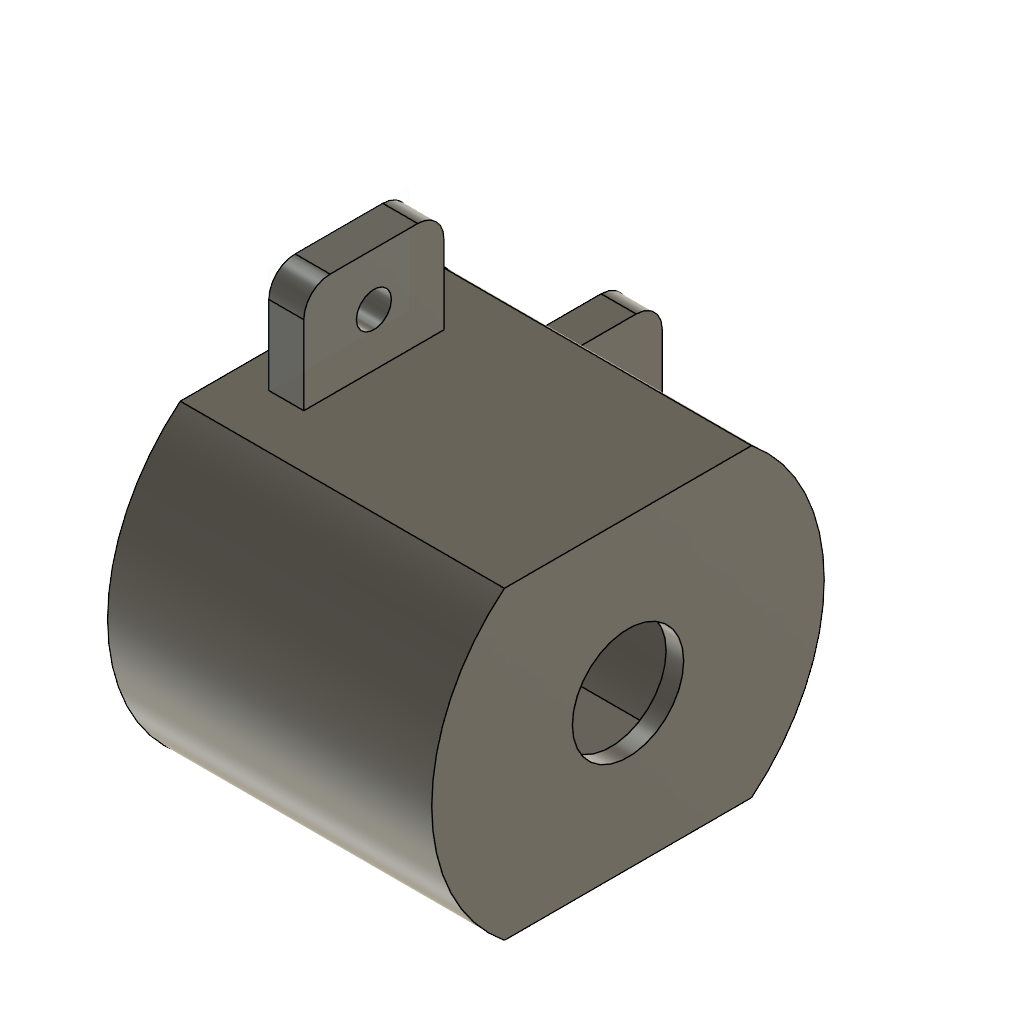
motorhalterung F-130 (Autodesk Fusion 360 design; units mm, degrees)
part number: 2026-11-07-18-57-53-680
Autodesk Fusion 360 part; units mm, degrees
sketch "Skizze1" plane through (0, 0, 0) normal (0, 0, 1) x (1, 0, 0)
  line L0 (0, 0) -> (26, 0)
  line L1 (26, 0) -> (26, 21)
  line L2 (26, 21) -> (0, 21)
  line L3 (0, 21) -> (0, 0)
  dimension "d1" = 21
  constraint coincident L0.start L3.end
  constraint horizontal L0
  constraint perpendicular L0 L1
  constraint perpendicular L1 L2
  constraint perpendicular L2 L3
  measures "d1" distance of L0.end L1.end
sketch "Skizze2" plane through (0, 0, 0) normal (0, 0, 1) x (1, 0, 0)
sketch "Skizze3" plane through (0, 0, 0) normal (1, 0, 0) x (0, 1, 0)
sketch "Skizze4" plane through (0, 0, 0) normal (1, 0, 0) x (0, 1, 0)
sketch "Skizze5" plane through (0, 0, 0) normal (1, 0, 0) x (0, 1, 0)
  line L0 (-6.6895, 0) -> (-6.6895, 7.7)
  line L1 (-6.6895, 0) -> (-6.6895, -7.7)
  line L2 (-6.6895, 7.7) -> (6.6895, 7.7)
  line L3 (-6.6895, -7.7) -> (6.6895, -7.7)
  line L4 (6.6895, 7.7) -> (6.6895, -7.7)
  arc A0 (-6.6895, 7.7) -> (-6.6895, -7.7) centre (0, 0) ccw
  arc A1 (6.6895, -7.7) -> (6.6895, 7.7) centre (0, 0) ccw
  dimension "d10" = 7.7
  dimension "d11" = 20.4
  constraint vertical L0
  constraint coincident A0.centre A1.centre
  constraint parallel L0 L1
  constraint perpendicular L0 L2
  constraint perpendicular L1 L3
  constraint concentric A0 A1
  measures "d10" distance of L0.start L0.end
  measures "d11" diameter of A0
extrude "Extrusion2" add sketch "Skizze5" along normal blind 17.5
shell "Schale1" thickness 1 outward yes removed faces 1 at (0, -2.914, 2.5667)
hole "Bohrung1" at (18.5, 0, 0) direction (-1, 0, 0) diameter 6.35 depth 5 tip angle 118
sketch "Skizze6" plane through (0, 0, 8.7) normal (0, 0, 1) x (-1, 0, 0)
  line L0 (0, -7.0533) -> (0, 7.0533)
  line L1 (0, 7.0533) -> (-18.5, 7.0533)
  line L2 (-18.5, 7.0533) -> (-18.5, -7.0533)
  line L3 (-18.5, -7.0533) -> (0, -7.0533)
  line L4 (-2, -4) -> (-4, -4)
  line L5 (-4, -4) -> (-4, 4)
  line L6 (-4, 4) -> (-2, 4)
  line L7 (-2, 4) -> (-2, -4)
  constraint horizontal L4
  constraint vertical L5
  constraint horizontal L6
  constraint vertical L7
extrude "Extrusion3" add sketch "Skizze6" along normal blind 6 contours L4 L5 L6 L7
sketch "Skizze7" plane through (2, 0, 0) normal (-1, 0, 0) x (0, -1, 0)
  line L0 (-4, 8.7) -> (4, 8.7)
  line L1 (4, 8.7) -> (4, 14.7)
  line L2 (4, 14.7) -> (-4, 14.7)
  line L3 (-4, 14.7) -> (-4, 8.7)
hole "Bohrung2" at (2, 0, 11.7001) direction (1, 0, 0) diameter 2 depth 5 tip angle 118
fillet "Abrundung1" radius 1.5 1 edges at (3, 4, 14.7)
fillet "Abrundung2" radius 1.5 1 edges at (3, -4, 14.7)
sketch "Skizze8" plane through (0, 0, 0) normal (0, 1, 0) x (1, 0, 0)
sketch "Skizze9" plane through (0, 0, 0) normal (1, 0, 0) x (0, 1, 0)
  line L0 (10.46, 4, 2) -> (16.46, 4, 2)
  line L1 (16.46, 4, 2) -> (16.46, -4, 2)
  line L2 (16.46, -4, 2) -> (10.46, -4, 2)
  line L3 (10.46, 4, 2) -> (10.46, -4, 2)
  dimension "d27" = 8
  dimension "d28" = 6
extrude "Extrusion4" add sketch "Skizze9" along normal blind 2 contours L0 L1 L2 L3 in plane through (2, 0, 0) normal (1, 0, 0)
fillet "Abrundung3" radius 1.5 1 edges at (3, 16.46, 4)
fillet "Abrundung4" radius 1.5 1 edges at (3, 16.46, -4)
hole "Bohrung3" at (2, 13.6499, 0) direction (1, 0, 0) diameter 2 depth 5 tip angle 118
